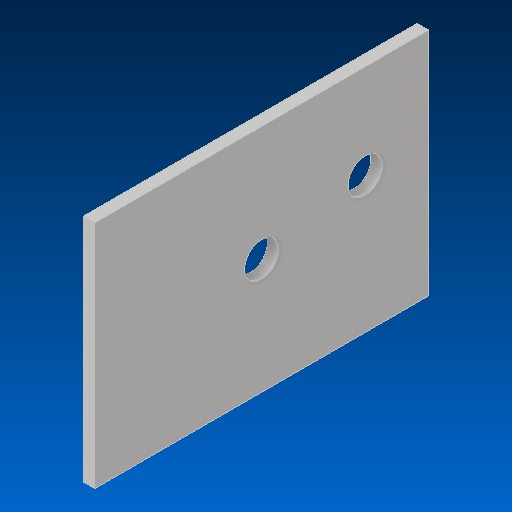
# Autodesk Inventor part: plates
Saved by Autodesk Inventor 2019 (Build 230136000, 136)
## iProperties
Created: 2019-04-16
Part Number: plates
Material: Generic
Document SubType Name: Modeling
Designer: Dell
Density: 1 g/cm^3
Appearance: Default
Author: Dell
Autodesk Inventor part; units mm, degrees
ref_plane "YZ Plane" through (0, 0, 0) normal (1, 0, 0) x (0, 1, 0)
ref_plane "XZ Plane" through (0, 0, 0) normal (0, 1, 0) x (-1, 0, 0)
ref_plane "XY Plane" through (0, 0, 0) normal (0, 0, 1) x (1, 0, 0)
sketch "Sketch1" plane through (0, 0, 0) normal (1, 0, 0) x (0, 1, 0)
  line L0 (10, -14.5) -> (-10, -14.5)
  line L1 (-10, -14.5) -> (-10, 14.5)
  line L2 (-10, 14.5) -> (10, 14.5)
  line L3 (10, 14.5) -> (10, -14.5)
  line L4 (10, -14.5) -> (-10, 14.5) construction
  line L5 (-10, -14.5) -> (10, 14.5) construction
  point P0 (0, 0)
  dimension "d0" = 20
  dimension "d1" = 29
  constraints: 12 end point, 2 midpoint, 2 parallel, 1 horizontal, 1 perpendicular
  measures "d0" distance of L1.end L2.end
  measures "d1" distance of L0.end L1.end
extrude "Extrusion1" add sketch "Sketch1" along normal blind 1
sketch "Sketch2" plane through (1, 0, 0) normal (1, 0, 0) x (0, 0, -1)
  circle A0 centre (9, 1.8036) radius 1.5 projected
  circle A1 centre (0, 0) radius 1.5
  ellipse E0 centre (-169.9783, 8.4608) end of major axis (-171.4783, 8.4608) minor radius 1.4527 projected
  dimension "d4" = 3
  constraints: 1 centre point, 1 coincident, 1 other
  measures "d4" diameter of A1
hole "Hole1" at (1, 1.8036, -9) at (1, 0, 0) direction (-1, 0, 0) diameter 3 end through all
body "Solid1"
